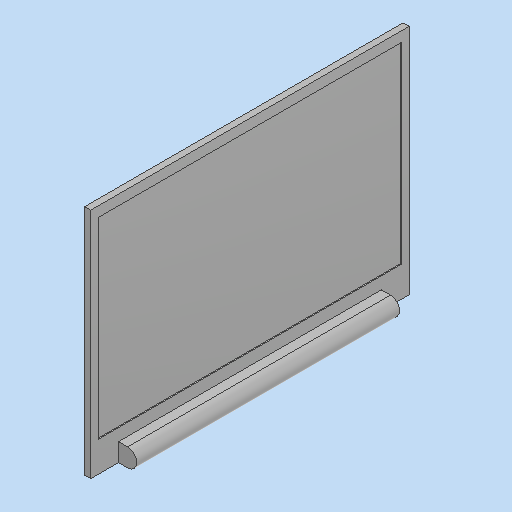
# Autodesk Inventor part: display
Saved by Autodesk Inventor 2025.3 (Build 293356030, 356C)
## iProperties
Created: 2025-08-02
Part Number: display
Material: 一般
Document SubType Name: Modeling
Designer: ibuki_ono
Density: 1 g/cm^3
Appearance: 滑らか - 標準の灰色
Author: ibuki_ono
Autodesk Inventor part; units mm, degrees
ref_plane "YZ Plane" through (0, 0, 0) normal (1, 0, 0) x (0, 1, 0)
ref_plane "XZ Plane" through (0, 0, 0) normal (0, 1, 0) x (-1, 0, 0)
ref_plane "XY Plane" through (0, 0, 0) normal (0, 0, 1) x (1, 0, 0)
sketch "スケッチ1" plane through (0, 0, 0) normal (1, 0, 0) x (0, 1, 0)
  line L0 (-115, -157.5) -> (115, -157.5)
  line L1 (115, -157.5) -> (115, 157.5)
  line L2 (115, 157.5) -> (-115, 157.5)
  line L3 (-115, 157.5) -> (-115, -157.5)
  line L4 (-115, -157.5) -> (115, 157.5) construction
  line L5 (115, -157.5) -> (-115, 157.5) construction
  point P0 (0, 0)
  dimension "d0" = 230
  dimension "d1" = 315
  constraints: 12 end point, 2 midpoint, 2 parallel, 1 horizontal, 1 perpendicular
  measures "d0" distance of L1.end L2.end
  measures "d1" distance of L0.end L1.end
extrude "押し出し1" add sketch "スケッチ1" along normal blind 6
sketch "スケッチ2" plane through (0, 0, 0) normal (0, 0, 1) x (1, 0, 0)
  line L0 (6, 115) -> (6, -115) projected
  circle A0 centre (15, -106) radius 9
  line L1 (0, -115) -> (6, -115) projected
  line L2 (15, -97) -> (6, -97)
  line L3 (15, -115) -> (6, -115)
  point P0 (0, 0)
  dimension "d4" = 18
  dimension "d5" = 9
  dimension "d6" = 9
  dimension "d7" = 9
  constraints: 4 end point, 2 point on circle, 2 tangent, 1 centre point, 1 point on line
  measures "d4" diameter of A0
  measures "d5" distance from line of L0 A0.centre
  measures "d6" distance from line of L1 A0.centre
  measures "d7" horizontal distance of A0.centre L2.end
extrude "押し出し2" add sketch "スケッチ2" along normal mid plane 260
sketch "スケッチ3" plane through (6, 0, 0) normal (1, 0, 0) x (0, 0, -1)
  line L0 (-150, -85) -> (150, -85)
  line L1 (150, -85) -> (150, 105)
  line L2 (150, 105) -> (-150, 105)
  line L3 (-150, 105) -> (-150, -85)
  line L4 (-150, -85) -> (150, 105) construction
  line L5 (150, -85) -> (-150, 105) construction
  line L6 (157.5, 115) -> (-157.5, 115) projected
  point P0 (0, 0)
  point P1 (0, 10)
  dimension "d10" = 300
  dimension "d11" = 190
  dimension "d12" = 10
  constraints: 12 end point, 2 midpoint, 2 parallel, 1 horizontal, 1 perpendicular, 1 vertical alignment
  measures "d10" distance of L2.end L1.end
  measures "d11" distance of L1.end L0.end
  measures "d12" distance between parallel lines of L2 L6
extrude "押し出し3" cut sketch "スケッチ3" against normal blind 1
equation "\"d7\" = d6"
